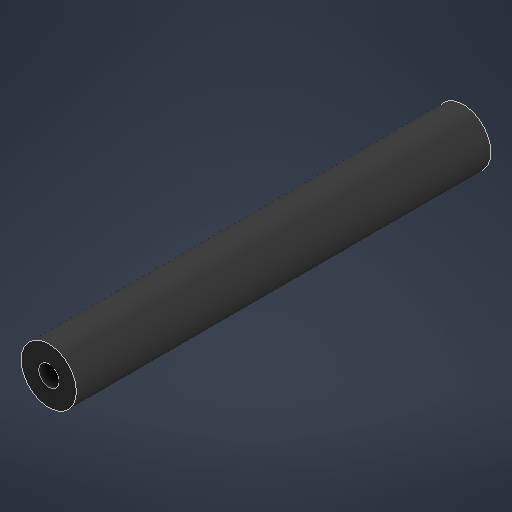
# Autodesk Inventor part: Stabilisatuer4.1
Saved by Autodesk Inventor 2026 (Build 300175050, 175E)
## iProperties
Created: 2025-04-25
Part Number: Stabilisatuer4.1
Material: Gummi
Document SubType Name: Modeling
Designer: karle
Density: 0.93 g/cm^3
Appearance: Gummi - Schwarz
Author: karle
Autodesk Inventor part; units mm, degrees
ref_plane "YZ Plane" through (0, 0, 0) normal (1, 0, 0) x (0, 1, 0)
ref_plane "XZ Plane" through (0, 0, 0) normal (0, 1, 0) x (-1, 0, 0)
ref_plane "XY Plane" through (0, 0, 0) normal (0, 0, 1) x (1, 0, 0)
sketch "Skizze1" plane through (0, 0, 0) normal (0, 0, 1) x (1, 0, 0)
  line L0 (0, 32.906) -> (0, -24.0171)
  line L1 (0, 150) -> (10, 150)
  line L2 (10, 150) -> (10, 0)
  line L3 (10, 0) -> (0, 0)
  line L4 (0, 0) -> (0, 150)
  point P0 (5, 0)
  point P1 (5, 150)
  dimension "d0" = 20
  dimension "d1" = 150
  constraints: 10 end point, 2 midpoint, 2 parallel, 1 horizontal, 1 perpendicular, 1 point on line, 1 vertical
  measures "d0" diameter of L2 L0
  measures "d1" distance of point (5, 0) point (5, 150)
revolve "Umdrehung1" add sketch "Skizze1" angle 360 about axis through (0, 32.906, 0) along (0, -1, 0)
sketch "Skizze3" plane through (0, 150, 0) normal (0, 1, 0) x (1, 0, 0)
  point P0 (0, 0)
  point P1 (0, 0)
  constraints: 1 coincident
hole "Bohrung1" at (0, 150, 0) direction (0, -1, 0) diameter 5.3 depth 20
sketch "Skizze4" plane through (0, 0, 0) normal (0, -1, 0) x (1, 0, 0)
  circle A0 centre (0, 0) radius 2.65 projected
  constraints: 1 coincident
hole "Bohrung2" at (0, 0, 0) direction (0, 1, 0) diameter 7.3 depth 20
